MOD-GRID Zippo Clip (Autodesk Fusion 360 design; units mm, degrees)
part number: 2026-10-23-11-05-04-811
Autodesk Fusion 360 part; units mm, degrees
ref_plane "WorkPlane97" through (2.5, 0, 0) normal (1, 0, 0) x (0, 1, 0)
sketch "Case section" plane through (2.5, 0, 0) normal (1, 0, 0) x (0, 0, -1)
  arc A0 (-6, 16.225) -> (-8.8, 19.025) centre (-8.8, 16.225) ccw
  arc A1 (-16.16, 19.025) -> (-18.96, 16.225) centre (-16.16, 16.225) ccw
  arc A2 (-18.96, -16.225) -> (-16.16, -19.025) centre (-16.16, -16.225) ccw
  arc A3 (-8.8, -19.025) -> (-6, -16.225) centre (-8.8, -16.225) ccw
  line L0 (-6, 16.225) -> (-6, -16.225)
  line L1 (-8.8, 19.025) -> (-16.16, 19.025)
  line L2 (-18.96, 16.225) -> (-18.96, -16.225)
  line L3 (-8.8, -19.025) -> (-16.16, -19.025)
extrude "Extrude231" add sketch "Case section" along normal blind 57.2 makes body 1
ref_plane "WorkPlane98" through (8.25, 0, 0) normal (1, 0, 0) x (0, 1, 0)
sketch "Band A body" plane through (8.25, 0, 0) normal (1, 0, 0) x (0, 0, -1)
  line L0 (0, -26.225) -> (-20.6855, -26.225)
  line L1 (-20.6855, -26.225) -> (-20.6855, 26.225)
  line L2 (-20.6855, 26.225) -> (0, 26.225)
  line L3 (0, 26.225) -> (0, -26.225)
extrude "Extrude232" add sketch "Band A body" along normal blind 8.25 and the other way blind 8.25 separate body makes body 2
fillet "Fillet49" radius 1.5 4 edges at (8.25, 26.225, 0) (8.25, -26.225, 0) (8.25, -26.225, 20.6855) (8.25, 26.225, 20.6855) on bodies 2
sketch "Band A cavity" plane through (8.25, 0, 0) normal (1, 0, 0) x (0, 0, -1)
  arc A0 (-6, 17.725) -> (-7.5, 19.225) centre (-7.5, 17.725) ccw
  arc A1 (-19.2026, 18.7422) -> (-18.637, 18.7422) centre (-18.9198, 19.025) ccw
  line L0 (-7.5, 19.225) -> (-18.1541, 19.225)
  line L1 (-18.1541, 19.225) -> (-18.637, 18.7422)
  line L2 (-19.2026, 18.7422) -> (-19.6855, 19.225)
  line L3 (-19.6855, 19.225) -> (-22.6855, 19.225)
  arc A2 (-7.5, -19.225) -> (-6, -17.725) centre (-7.5, -17.725) ccw
  arc A3 (-18.637, -18.7422) -> (-19.2026, -18.7422) centre (-18.9198, -19.025) ccw
  line L4 (-7.5, -19.225) -> (-18.1541, -19.225)
  line L5 (-18.1541, -19.225) -> (-18.637, -18.7422)
  line L6 (-19.2026, -18.7422) -> (-19.6855, -19.225)
  line L7 (-19.6855, -19.225) -> (-22.6855, -19.225)
  line L8 (-6, -17.725) -> (-6, 17.725)
  line L9 (-22.6855, -19.225) -> (-22.6855, 19.225)
extrude "Extrude233" cut sketch "Band A cavity" along normal blind 16.5 and the other way blind 16.5 bodies 2
sketch "Band A relief" plane through (8.25, 0, 0) normal (1, 0, 0) x (0, 0, -1)
  arc A0 (-3.4593, 16.2543) -> (-7.5, 22.025) centre (-7.5, 17.725) ccw
  arc A1 (-2.3317, 15.8439) -> (-7.5, 23.225) centre (-7.5, 17.725) ccw
  line L0 (-7.5, 22.025) -> (-11.5, 21.225)
  line L1 (-11.5, 21.225) -> (-22.6855, 21.225)
  line L2 (-22.6855, 21.225) -> (-22.6855, 23.225)
  line L3 (-22.6855, 23.225) -> (-7.5, 23.225)
  line L4 (-2.3317, 15.8439) -> (-3.4593, 16.2543)
  circle A2 centre (-2.8955, 16.0491) radius 0.6
  arc A3 (-7.5, -22.025) -> (-3.4593, -16.2543) centre (-7.5, -17.725) ccw
  arc A4 (-7.5, -23.225) -> (-2.3317, -15.8439) centre (-7.5, -17.725) ccw
  line L5 (-7.5, -22.025) -> (-11.5, -21.225)
  line L6 (-11.5, -21.225) -> (-22.6855, -21.225)
  line L7 (-22.6855, -21.225) -> (-22.6855, -23.225)
  line L8 (-22.6855, -23.225) -> (-7.5, -23.225)
  line L9 (-2.3317, -15.8439) -> (-3.4593, -16.2543)
  circle A5 centre (-2.8955, -16.0491) radius 0.6
extrude "Extrude234" cut sketch "Band A relief" along normal blind 16.5 and the other way blind 16.5 bodies 2
ref_plane "WorkPlane99" through (0, 0, 0) normal (1, 0, 0) x (0, 1, 0)
sketch "Band A stop" plane through (0, 0, 0) normal (1, 0, 0) x (0, 0, -1)
  line L0 (-6, -15.025) -> (-6, 15.025)
  line L1 (-6, 15.025) -> (-14, 15.025)
  line L2 (-14, 15.025) -> (-14, 12.025)
  line L3 (-14, 12.025) -> (-9, 12.025)
  line L4 (-9, 12.025) -> (-9, -12.025)
  line L5 (-9, -12.025) -> (-14, -12.025)
  line L6 (-14, -12.025) -> (-14, -15.025)
  line L7 (-14, -15.025) -> (-6, -15.025)
extrude "Extrude235" add sketch "Band A stop" along normal blind 2.5 bodies 2
fillet "Fillet50" radius 1.5 4 edges at (1.25, -12.025, 9) (1.25, 12.025, 9) (1.25, 15.025, 6) (1.25, -15.025, 6) on bodies 2
fillet "Fillet51" radius 0.8 4 edges at (1.25, -15.025, 14) (1.25, -12.025, 14) (1.25, 12.025, 14) (1.25, 15.025, 14) on bodies 2
chamfer "Chamfer47" distance 0.5 angle 45 32 edges at (0, 14.7907, 13.7657) (0, 13.525, 14) (0, 12.2593, 13.7657) (0, 12.025, 11.85) (0, 11.5857, 9.4393) (0, 0, 9) (0, -11.5857, 9.4393) (0, -12.025, 11.85) (0, -12.2593, 13.7657) (0, -13.525, 14) (0, -14.7907, 13.7657) (0, -15.025, 10.35) (0, -15.4643, 6.4393) (0, -17.125, 6) (0, -18.7857, 6.4393) (0, -19.225, 12.8271) (0, 15.025, 10.35) (0, 15.4643, 6.4393) (0, 17.125, 6) (0, 18.7857, 6.4393) (0, 19.225, 12.8271) (0, 20.225, 20.6855) (0, 23.975, 20.6855) (0, 25.7857, 20.2461) (0, 26.225, 10.3427) (0, 25.7857, 0.4393) (0, 0, 0) (0, -25.7857, 0.4393) (0, -26.225, 10.3427) (0, -25.7857, 20.2461) (0, -23.975, 20.6855) (0, -20.225, 20.6855) tangent chain off on bodies 2
ref_plane "WorkPlane100" through (0, 0, 0) normal (1, 0, 0) x (0, 1, 0)
sketch "Band A legs" plane through (0, 0, 0) normal (1, 0, 0) x (0, 0, -1)
  line L0 (-0.5, -13.45) -> (4.64, -13.45)
  line L1 (4.64, -13.45) -> (4.64, -13.93)
  line L2 (4.64, -13.93) -> (3.4, -15.19)
  line L3 (3.4, -15.19) -> (3.1, -14.32)
  line L4 (3.1, -14.32) -> (-0.5, -14.32)
  line L5 (-0.5, -14.32) -> (-0.5, -13.45)
  line L6 (-0.5, -10.55) -> (4.64, -10.55)
  line L7 (4.64, -10.55) -> (4.64, -10.07)
  line L8 (4.64, -10.07) -> (3.4, -8.81)
  line L9 (3.4, -8.81) -> (3.1, -9.68)
  line L10 (3.1, -9.68) -> (-0.5, -9.68)
  line L11 (-0.5, -9.68) -> (-0.5, -10.55)
  line L12 (-0.5, 10.55) -> (4.64, 10.55)
  line L13 (4.64, 10.55) -> (4.64, 10.07)
  line L14 (4.64, 10.07) -> (3.4, 8.81)
  line L15 (3.4, 8.81) -> (3.1, 9.68)
  line L16 (3.1, 9.68) -> (-0.5, 9.68)
  line L17 (-0.5, 9.68) -> (-0.5, 10.55)
  line L18 (-0.5, 13.45) -> (4.64, 13.45)
  line L19 (4.64, 13.45) -> (4.64, 13.93)
  line L20 (4.64, 13.93) -> (3.4, 15.19)
  line L21 (3.4, 15.19) -> (3.1, 14.32)
  line L22 (3.1, 14.32) -> (-0.5, 14.32)
  line L23 (-0.5, 14.32) -> (-0.5, 13.45)
extrude "Extrude236" add sketch "Band A legs" along normal blind 4.76 bodies 2
ref_plane "WorkPlane101" through (47, 0, 0) normal (1, 0, 0) x (0, 1, 0)
sketch "Band B body" plane through (47, 0, 0) normal (1, 0, 0) x (0, 0, -1)
  line L0 (0, -26.225) -> (-20.6855, -26.225)
  line L1 (-20.6855, -26.225) -> (-20.6855, 26.225)
  line L2 (-20.6855, 26.225) -> (0, 26.225)
  line L3 (0, 26.225) -> (0, -26.225)
extrude "Extrude237" add sketch "Band B body" along normal blind 7 and the other way blind 7 separate body makes body 3
fillet "Fillet52" radius 1.5 4 edges at (47, 26.225, 0) (47, -26.225, 0) (47, -26.225, 20.6855) (47, 26.225, 20.6855) on bodies 3
sketch "Band B cavity" plane through (47, 0, 0) normal (1, 0, 0) x (0, 0, -1)
  arc A0 (-6, 17.725) -> (-7.5, 19.225) centre (-7.5, 17.725) ccw
  arc A1 (-19.2026, 18.7422) -> (-18.637, 18.7422) centre (-18.9198, 19.025) ccw
  line L0 (-7.5, 19.225) -> (-18.1541, 19.225)
  line L1 (-18.1541, 19.225) -> (-18.637, 18.7422)
  line L2 (-19.2026, 18.7422) -> (-19.6855, 19.225)
  line L3 (-19.6855, 19.225) -> (-22.6855, 19.225)
  arc A2 (-7.5, -19.225) -> (-6, -17.725) centre (-7.5, -17.725) ccw
  arc A3 (-18.637, -18.7422) -> (-19.2026, -18.7422) centre (-18.9198, -19.025) ccw
  line L4 (-7.5, -19.225) -> (-18.1541, -19.225)
  line L5 (-18.1541, -19.225) -> (-18.637, -18.7422)
  line L6 (-19.2026, -18.7422) -> (-19.6855, -19.225)
  line L7 (-19.6855, -19.225) -> (-22.6855, -19.225)
  line L8 (-6, -17.725) -> (-6, 17.725)
  line L9 (-22.6855, -19.225) -> (-22.6855, 19.225)
extrude "Extrude238" cut sketch "Band B cavity" along normal blind 14 and the other way blind 14 bodies 3
sketch "Band B relief" plane through (47, 0, 0) normal (1, 0, 0) x (0, 0, -1)
  arc A0 (-3.4593, 16.2543) -> (-7.5, 22.025) centre (-7.5, 17.725) ccw
  arc A1 (-2.3317, 15.8439) -> (-7.5, 23.225) centre (-7.5, 17.725) ccw
  line L0 (-7.5, 22.025) -> (-11.5, 21.225)
  line L1 (-11.5, 21.225) -> (-22.6855, 21.225)
  line L2 (-22.6855, 21.225) -> (-22.6855, 23.225)
  line L3 (-22.6855, 23.225) -> (-7.5, 23.225)
  line L4 (-2.3317, 15.8439) -> (-3.4593, 16.2543)
  circle A2 centre (-2.8955, 16.0491) radius 0.6
  arc A3 (-7.5, -22.025) -> (-3.4593, -16.2543) centre (-7.5, -17.725) ccw
  arc A4 (-7.5, -23.225) -> (-2.3317, -15.8439) centre (-7.5, -17.725) ccw
  line L5 (-7.5, -22.025) -> (-11.5, -21.225)
  line L6 (-11.5, -21.225) -> (-22.6855, -21.225)
  line L7 (-22.6855, -21.225) -> (-22.6855, -23.225)
  line L8 (-22.6855, -23.225) -> (-7.5, -23.225)
  line L9 (-2.3317, -15.8439) -> (-3.4593, -16.2543)
  circle A5 centre (-2.8955, -16.0491) radius 0.6
extrude "Extrude239" cut sketch "Band B relief" along normal blind 14 and the other way blind 14 bodies 3
chamfer "Chamfer48" distance 0.5 angle 45 16 edges at (40, 23.975, 20.6855) (40, 25.7857, 20.2461) (40, 26.225, 10.3427) (40, 25.7857, 0.4393) (40, 0, 0) (40, -25.7857, 0.4393) (40, -26.225, 10.3427) (40, -25.7857, 20.2461) (40, -23.975, 20.6855) (40, -20.225, 20.6855) (40, -19.225, 12.8271) (40, -18.7857, 6.4393) (40, 0, 6) (40, 18.7857, 6.4393) (40, 19.225, 12.8271) (40, 20.225, 20.6855) tangent chain off on bodies 3
ref_plane "WorkPlane102" through (40, 0, 0) normal (1, 0, 0) x (0, 1, 0)
sketch "Band B legs" plane through (40, 0, 0) normal (1, 0, 0) x (0, 0, -1)
  line L0 (-0.5, -13.45) -> (4.64, -13.45)
  line L1 (4.64, -13.45) -> (4.64, -13.93)
  line L2 (4.64, -13.93) -> (3.4, -15.19)
  line L3 (3.4, -15.19) -> (3.1, -14.32)
  line L4 (3.1, -14.32) -> (-0.5, -14.32)
  line L5 (-0.5, -14.32) -> (-0.5, -13.45)
  line L6 (-0.5, -10.55) -> (4.64, -10.55)
  line L7 (4.64, -10.55) -> (4.64, -10.07)
  line L8 (4.64, -10.07) -> (3.4, -8.81)
  line L9 (3.4, -8.81) -> (3.1, -9.68)
  line L10 (3.1, -9.68) -> (-0.5, -9.68)
  line L11 (-0.5, -9.68) -> (-0.5, -10.55)
  line L12 (-0.5, 10.55) -> (4.64, 10.55)
  line L13 (4.64, 10.55) -> (4.64, 10.07)
  line L14 (4.64, 10.07) -> (3.4, 8.81)
  line L15 (3.4, 8.81) -> (3.1, 9.68)
  line L16 (3.1, 9.68) -> (-0.5, 9.68)
  line L17 (-0.5, 9.68) -> (-0.5, 10.55)
  line L18 (-0.5, 13.45) -> (4.64, 13.45)
  line L19 (4.64, 13.45) -> (4.64, 13.93)
  line L20 (4.64, 13.93) -> (3.4, 15.19)
  line L21 (3.4, 15.19) -> (3.1, 14.32)
  line L22 (3.1, 14.32) -> (-0.5, 14.32)
  line L23 (-0.5, 14.32) -> (-0.5, 13.45)
extrude "Extrude240" add sketch "Band B legs" along normal blind 4.76 bodies 3
equation "zippo_w = 38.05 mm" comment "Zippo width, parallel to the plate"
equation "zippo_t = 12.96 mm" comment "Zippo thickness, away from the plate"
equation "zippo_clear = 0.3 mm" comment "Clearance added to the cavity"
equation "cav_w = zippo_w + zippo_clear" comment "Cavity width"
equation "cav_t = zippo_t + zippo_clear" comment "Cavity thickness"
equation "cav_r = 1.50 mm" comment "Cavity end radius (the obround ends)"
equation "cav_cy = ( cav_w - cav_t ) / 2" comment "Cavity end-arc centre, off the middle"
equation "base_t = 6.00 mm" comment "Base under the lighter"
equation "cav_cz = base_t + cav_r" comment "Cavity centre height"
equation "arm_t = 1.60 mm" comment "CONSTANT arm thickness - 5 perimeters at 0.4"
equation "relief_w = 1.20 mm" comment "Relief slot width behind the arm"
equation "relief_a0 = -110 deg" comment "Relief slot root angle; lower = longer, softer arm"
equation "rail_t = 3.00 mm" comment "Outer rail beyond the relief slot"
equation "arm_spread = 0.4 mm" comment "Total spread to seat/release the lighter"
equation "lead_in = 1.2 mm" comment "45 deg lead-in above the lip tips"
equation "land_h = 1.00 mm" comment "Band height above the lip tips"
equation "band_len = 14.0 mm" comment "Band width along the lighter = part height when printed"
equation "grid_pitch = 8 mm" comment "MOD-GRID pitch"
equation "leg_pair_y = 12.0 mm" comment "Leg pairs at +/- this; 24 mm apart = 3 cells"
equation "leg_hole_len = 4.90 mm - leg_clear" comment "Leg extent along the lighter axis; 0.10 clearance in the 5.00 hole"
equation "leg_inner_hw = 1.45 mm" comment "Leg inner face from pair centre -> 2.90 gap"
equation "leg_shank_hw = 2.39 mm - leg_clear / 2" comment "Relaxed shank half-span -> 4.78 pair"
equation "barb_hw = 3.19 mm" comment "Barb peak half-span -> 6.38 pair, squeezes 1.38"
equation "barb_z = -3.40 mm" comment "Barb peak depth below the seating face"
equation "catch_z = -3.10 mm" comment "Catch face: 0.10 below the 3.00 plate"
equation "leg_tip_z = -4.64 mm" comment "Leg tip"
equation "leg_tip_hw = 2.00 mm - leg_clear / 2" comment "Tip half-span, sets the ~45 deg lead-in"
equation "body_corner_r = 1.50 mm" comment "Rounded outer corners"
equation "first_layer_cham = 0.50 mm" comment "Elephant-foot chamfer on the bed face"
equation "id_dimple_d = 1.6 mm" comment "Identification dimple diameter"
equation "id_dimple_h = 0.6 mm" comment "Identification dimple depth"
equation "band_hw = cav_hw + arm_root + relief_w + rail_t" comment "Band half width"
equation "lip_tip_y = zippo_w / 2 - lip_over" comment "Lip tip, inside the lighter half width by half the spread"
equation "lip_tip_z = cav_cz + sqrt(cav_r ^ 2 - ( lip_tip_y - cav_cy ) ^ 2)" comment "Lip tip height on the cavity arc"
equation "band_h = lip_z0 + 2 * lip_proj + land_h" comment "Band overall height"
equation "leg_clear = 0.14 mm" comment "Shrinks the leg LENGTH and SHANK (not the barb). 0 = official nominal (4.90 long, 4.78 shank) which assumes the hole prints a true 5.00; FDM holes usually come out undersize, so raise this if the legs crush going in. MEASURED: the printed hole came out 0.14 under nominal, i.e. 0.07 per wall. External features run over by the same bias, so a 4.90 leg prints ~5.04; 0.14 here brings the PRINTED leg back to 4.90 in a true 5.00 hole. Zero it if the printer is dimensionally calibrated."
equation "zippo_len = 57.20 mm" comment "Case length - only sets where the reference body ends"
equation "case_r = 2.80 mm" comment "PHOTO ESTIMATE of the cross-section corner radius, scaled off the known 38.05 width. It is NOT 6.48 - the case is a rounded rectangle, not an obround. Used for the reference body and to place the bead; the cavity deliberately does not depend on it."
equation "cav_clear = 0.40 mm" comment "Clearance on the cavity width (total)"
equation "cav_hw = ( zippo_w + cav_clear ) / 2" comment "Cavity half width"
equation "lip_over = 0.40 mm" comment "How far each bead reaches inboard of the case's side face. This IS the capture: the case cannot rise without splaying each arm by this much."
equation "bead_r = lip_over + cav_clear / 2" comment "Bead radius - equal to the reach by construction, which makes the bead a HALF CIRCLE tangent to the cavity wall above and below. No tooth, no tip, nothing to snap off."
equation "bead_clear = 0.10 mm" comment "Clearance between bead and case when seated"
equation "bead_z = base_t + zippo_t + bead_above" comment "Bead centre height - DERIVED by run() as the lowest it can sit without fouling the case's top corner radius."
equation "band_a_x = 0 mm" comment "Band A bed face"
equation "band_cells = 5" comment "Grid cells between the two bands"
equation "band_b_x = band_a_x + band_cells * grid_pitch" comment "Band B bed face"
equation "bead_above = 0.10 mm" comment "Bead centre height ABOVE the case's top face. The previous version derived the bead as \"just tangent to the case's corner radius\", which put its centre 0.5 mm BELOW the top face - so the bead met the corner on the SIDE of the case instead of capturing over the top, and the lighter sat loose with the arms touching its flanks. Capture has to happen above the top face."
equation "arm_root = 2.80 mm" comment "Arm thickness AT THE ROOT = 7 extrusions at 0.4. The arm is TAPERED, thick at the base and thinner at the tip, because the bending moment is largest at the root and nearly zero at the bead. A thick root also pushes the relief slot further out, which is what gives the root web its thickness - see root_web()."
equation "arm_tip = 2.00 mm" comment "Arm thickness at the bead = 5 extrusions. Keep every flexure wall an integer multiple of the extrusion width and >= 4 of them: 1.2 mm is 2.86 extrusions, so the slicer lays a gap-fill bond line down the middle of the flexure."
equation "arm_blend = 4.00 mm" comment "Height above the cavity corner over which arm_root blends down to arm_tip. A step here would be a stress riser; blending over several mm keeps the thick material where the moment is and still leaves most of the arm compliant."
equation "case_r_min = 2.00 mm" comment "The SQUAREST corner the case could plausibly have. The capture lip is positioned so that it still clears THIS at seated, which is the recoverable bias: a squarer-than-expected case can never be held proud, while a rounder one only lifts a little further before the lip bites. Lowering it tightens the catch and risks the part not seating."
equation "lip_clear = 0.40 mm" comment "Gap between the lip's underside and the case's top corner when seated, evaluated at case_r_min. The arms are UNLOADED when the case is home, so there is no creep."
equation "lip_tipr = 0.40 mm" comment "Radius on the lip tip = ONE NOZZLE WIDTH. A knife edge will not print. It also sets the only part of the stroke where the contact normal can reach horizontal: a flat land of width L parks the case for L of travel, a radius parks it for 2*r*sin(arctan mu) ~ 0.23 mm and gives a 45 deg cam immediately below. That difference is the whole fix over the bead version."
equation "lip_apex_y = lip_tip_y - 0.4142135624 * lip_tipr" comment "Virtual apex where the two 45 deg faces would meet if the tip were not rounded"
equation "lip_proj = cav_hw - lip_apex_y" comment "How far the apex stands proud of the cavity wall. At 45 deg this is also the RISE of each face, so the lip is 2 * lip_proj tall."
equation "lip_z0 = 1.4142135624 * ( case_r_min + lip_clear ) + zippo_w / 2 + base_t + zippo_t - 2 * case_r_min - cav_hw" comment "Foot of the capture ramp, where the 45 deg underside leaves the cavity wall. Derived, not chosen: the underside is the line y + z = cav_hw + lip_z0, and this is the lowest it can sit while still standing lip_clear off a case corner of radius case_r_min centred at (zippo_w/2 - r, base_t + zippo_t - r). Lower and a square-cornered case is held proud - the exact failure of the bead version."
equation "lip_zt = lip_z0 + lip_proj" comment "Height of the lip tip = where the load is applied to the arm"
equation "stop_t = 2.50 mm" comment "Thickness of the C stop along the lighter's axis. It sits at Band A's BED FACE, i.e. in the first 2.5 mm of the print, so it is laid straight onto the build plate - no overhang anywhere and it helps adhesion. Band A is lengthened by this much so the gripping length stays a full band_len."
equation "stop_w = 3.00 mm" comment "Limb width of the C. 3.00 survives a 0.50 bed chamfer on both sides with 2 mm left."
equation "stop_gap = 1.20 mm" comment "Gap between the C's limbs and the cavity wall. THIS IS THE POINT OF THE C: it keeps the stop attached to the solid BASE only and clear of the flexing arms. A stop that reached the cavity walls would brace the arms over 2.5 mm of their length, stiffening them exactly at the root where the bending moment peaks."
equation "stop_h = 8.00 mm" comment "How far the C's limbs rise above the cavity floor. The lighter's end face is 12.96 tall, so this catches the bottom 8 mm of it across the full width - far more than a 65 g lighter needs - while leaving the top open so the lighter still drops straight into the band."
equation "stop_hw = cav_hw - cav_r - stop_blend - stop_gap" comment "C half width"
equation "band_a_len = band_len + stop_t" comment "Band A overall - the stop plus a full gripping length"
equation "zippo_x0 = band_a_x + stop_t" comment "The lighter's bottom end, butted against the C stop."
equation "stop_blend = 1.50 mm" comment "Fillet where the C's limbs grow out of the cavity floor, and on the inside corners of the C. This is the transition that was wrong in rev E: stop_hw was measured off cav_hw, which ignored that the floor stops being FLAT at cav_hw - cav_r. The limbs landed 0.50 mm from the bottom corner arc, so there was no room for a fillet at all and the junction came out as a cramped sliver."
equation "stop_edge_r = 0.80 mm" comment "Round on the C's free top edges, so it does not read as a raw extruded U."
equation "d1166 = zippo_x0"
equation "d1168 = zippo_len"
equation "d1170 = band_a_x + band_a_len / 2"
equation "d1172 = band_a_len / 2"
equation "d1174 = band_a_len / 2"
equation "d1177 = body_corner_r"
equation "d1178 = band_a_len"
equation "d1180 = band_a_len"
equation "d1182 = band_a_len"
equation "d1184 = band_a_len"
equation "d1186 = band_a_x"
equation "d1188 = stop_t"
equation "d1191 = stop_blend"
equation "d1193 = stop_edge_r"
equation "d1194 = first_layer_cham"
equation "d1195 = band_a_x"
equation "d1197 = leg_hole_len"
equation "d1199 = band_b_x + band_len / 2"
equation "d1201 = band_len / 2"
equation "d1203 = band_len / 2"
equation "d1206 = body_corner_r"
equation "d1207 = band_len"
equation "d1209 = band_len"
equation "d1211 = band_len"
equation "d1213 = band_len"
equation "d1215 = first_layer_cham"
equation "d1216 = band_b_x"
equation "d1218 = leg_hole_len"
named bodies: "Reference - Zippo", "Band A", "Band B"
